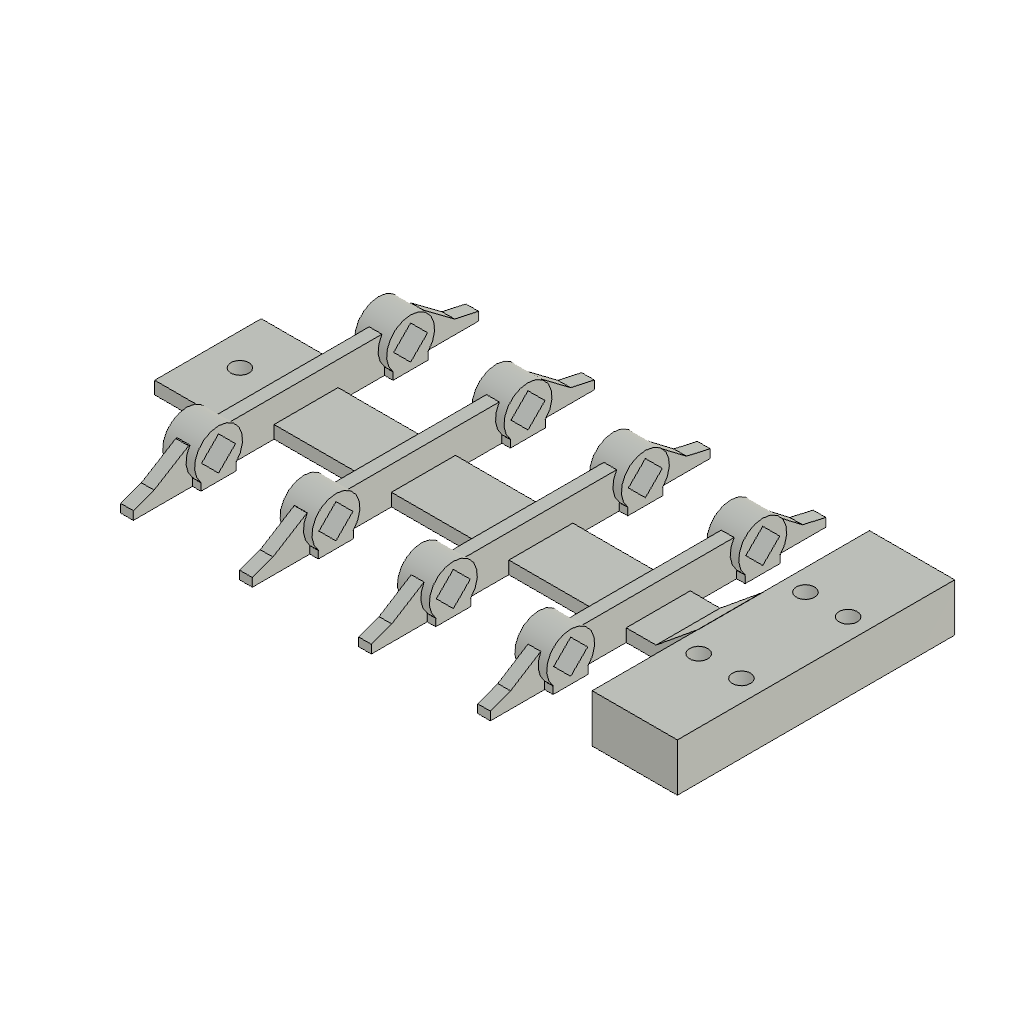
wing_tip (Autodesk Fusion 360 design; units mm, degrees)
part number: 2026-10-10-17-06-18-899
Autodesk Fusion 360 part; units mm, degrees
sketch "Continuous connecting strip sketch" plane through (0, 0, 0) normal (0, 0, 1) x (1, 0, 0)
  line L0 (0, -6) -> (114, -6)
  line L1 (114, -6) -> (114, 6)
  line L2 (114, 6) -> (0, 6)
  line L3 (0, 6) -> (0, -6)
extrude "Continuous connecting strip" add sketch "Continuous connecting strip sketch" along normal blind 2.4
ref_plane "WorkPlane1" through (16, 0, 0) normal (1, 0, 0) x (0, 1, 0)
sketch "Rib at 16 mm sketch" plane through (16, 0, 0) normal (1, 0, 0) x (0, 0, -1)
  line L0 (0, -32.3749) -> (0, 32.3749)
  line L1 (0, 32.3749) -> (-1.6, 32.3749)
  line L2 (-1.6, 32.3749) -> (-2.6, 27.8424)
  line L3 (-2.6, 27.8424) -> (-6.95, 22.0149)
  line L4 (-6.95, 22.0149) -> (-6.95, -22.0149)
  line L5 (-6.95, -22.0149) -> (-3, -28.4899)
  line L6 (-3, -28.4899) -> (-1.6, -32.3749)
  line L7 (-1.6, -32.3749) -> (0, -32.3749)
extrude "Rib at 16 mm" add sketch "Rib at 16 mm sketch" along normal blind 2.4
ref_plane "WorkPlane2" through (14, 0, 0) normal (1, 0, 0) x (0, 1, 0)
sketch "front short guide at 16 mm sketch" plane through (14, 0, 0) normal (1, 0, 0) x (0, 0, -1)
  circle A0 centre (-4.5, -18) radius 4.5
extrude "front short guide at 16 mm" add sketch "front short guide at 16 mm sketch" along normal blind 6
sketch "front guide foot at 16 mm sketch" plane through (0, 0, 0) normal (0, 0, 1) x (1, 0, 0)
  line L0 (14, -21.3) -> (20, -21.3)
  line L1 (20, -21.3) -> (20, -14.7)
  line L2 (20, -14.7) -> (14, -14.7)
  line L3 (14, -14.7) -> (14, -21.3)
extrude "front guide foot at 16 mm" add sketch "front guide foot at 16 mm sketch" along normal blind 1.4
ref_plane "WorkPlane3" through (14, 0, 0) normal (1, 0, 0) x (0, 1, 0)
sketch "rear short guide at 16 mm sketch" plane through (14, 0, 0) normal (1, 0, 0) x (0, 0, -1)
  circle A0 centre (-4.5, 18) radius 4.5
extrude "rear short guide at 16 mm" add sketch "rear short guide at 16 mm sketch" along normal blind 6
sketch "rear guide foot at 16 mm sketch" plane through (0, 0, 0) normal (0, 0, 1) x (1, 0, 0)
  line L0 (14, 14.7) -> (20, 14.7)
  line L1 (20, 14.7) -> (20, 21.3)
  line L2 (20, 21.3) -> (14, 21.3)
  line L3 (14, 21.3) -> (14, 14.7)
extrude "rear guide foot at 16 mm" add sketch "rear guide foot at 16 mm sketch" along normal blind 1.4
ref_plane "WorkPlane4" through (38, 0, 0) normal (1, 0, 0) x (0, 1, 0)
sketch "Rib at 38 mm sketch" plane through (38, 0, 0) normal (1, 0, 0) x (0, 0, -1)
  line L0 (0, -32.0662) -> (0, 32.0662)
  line L1 (0, 32.0662) -> (-1.6, 32.0662)
  line L2 (-1.6, 32.0662) -> (-2.6, 27.5769)
  line L3 (-2.6, 27.5769) -> (-6.95, 21.805)
  line L4 (-6.95, 21.805) -> (-6.95, -21.805)
  line L5 (-6.95, -21.805) -> (-3, -28.2183)
  line L6 (-3, -28.2183) -> (-1.6, -32.0662)
  line L7 (-1.6, -32.0662) -> (0, -32.0662)
extrude "Rib at 38 mm" add sketch "Rib at 38 mm sketch" along normal blind 2.4
ref_plane "WorkPlane5" through (36, 0, 0) normal (1, 0, 0) x (0, 1, 0)
sketch "front short guide at 38 mm sketch" plane through (36, 0, 0) normal (1, 0, 0) x (0, 0, -1)
  circle A0 centre (-4.5, -18) radius 4.5
extrude "front short guide at 38 mm" add sketch "front short guide at 38 mm sketch" along normal blind 6
sketch "front guide foot at 38 mm sketch" plane through (0, 0, 0) normal (0, 0, 1) x (1, 0, 0)
  line L0 (36, -21.3) -> (42, -21.3)
  line L1 (42, -21.3) -> (42, -14.7)
  line L2 (42, -14.7) -> (36, -14.7)
  line L3 (36, -14.7) -> (36, -21.3)
extrude "front guide foot at 38 mm" add sketch "front guide foot at 38 mm sketch" along normal blind 1.4
ref_plane "WorkPlane6" through (36, 0, 0) normal (1, 0, 0) x (0, 1, 0)
sketch "rear short guide at 38 mm sketch" plane through (36, 0, 0) normal (1, 0, 0) x (0, 0, -1)
  circle A0 centre (-4.5, 18) radius 4.5
extrude "rear short guide at 38 mm" add sketch "rear short guide at 38 mm sketch" along normal blind 6
sketch "rear guide foot at 38 mm sketch" plane through (0, 0, 0) normal (0, 0, 1) x (1, 0, 0)
  line L0 (36, 14.7) -> (42, 14.7)
  line L1 (42, 14.7) -> (42, 21.3)
  line L2 (42, 21.3) -> (36, 21.3)
  line L3 (36, 21.3) -> (36, 14.7)
extrude "rear guide foot at 38 mm" add sketch "rear guide foot at 38 mm sketch" along normal blind 1.4
ref_plane "WorkPlane7" through (60, 0, 0) normal (1, 0, 0) x (0, 1, 0)
sketch "Rib at 60 mm sketch" plane through (60, 0, 0) normal (1, 0, 0) x (0, 0, -1)
  line L0 (0, -31.7576) -> (0, 31.7576)
  line L1 (0, 31.7576) -> (-1.6, 31.7576)
  line L2 (-1.6, 31.7576) -> (-2.6, 27.3115)
  line L3 (-2.6, 27.3115) -> (-6.95, 21.5952)
  line L4 (-6.95, 21.5952) -> (-6.95, -21.5952)
  line L5 (-6.95, -21.5952) -> (-3, -27.9467)
  line L6 (-3, -27.9467) -> (-1.6, -31.7576)
  line L7 (-1.6, -31.7576) -> (0, -31.7576)
extrude "Rib at 60 mm" add sketch "Rib at 60 mm sketch" along normal blind 2.4
ref_plane "WorkPlane8" through (58, 0, 0) normal (1, 0, 0) x (0, 1, 0)
sketch "front short guide at 60 mm sketch" plane through (58, 0, 0) normal (1, 0, 0) x (0, 0, -1)
  circle A0 centre (-4.5, -18) radius 4.5
extrude "front short guide at 60 mm" add sketch "front short guide at 60 mm sketch" along normal blind 6
sketch "front guide foot at 60 mm sketch" plane through (0, 0, 0) normal (0, 0, 1) x (1, 0, 0)
  line L0 (58, -21.3) -> (64, -21.3)
  line L1 (64, -21.3) -> (64, -14.7)
  line L2 (64, -14.7) -> (58, -14.7)
  line L3 (58, -14.7) -> (58, -21.3)
extrude "front guide foot at 60 mm" add sketch "front guide foot at 60 mm sketch" along normal blind 1.4
ref_plane "WorkPlane9" through (58, 0, 0) normal (1, 0, 0) x (0, 1, 0)
sketch "rear short guide at 60 mm sketch" plane through (58, 0, 0) normal (1, 0, 0) x (0, 0, -1)
  circle A0 centre (-4.5, 18) radius 4.5
extrude "rear short guide at 60 mm" add sketch "rear short guide at 60 mm sketch" along normal blind 6
sketch "rear guide foot at 60 mm sketch" plane through (0, 0, 0) normal (0, 0, 1) x (1, 0, 0)
  line L0 (58, 14.7) -> (64, 14.7)
  line L1 (64, 14.7) -> (64, 21.3)
  line L2 (64, 21.3) -> (58, 21.3)
  line L3 (58, 21.3) -> (58, 14.7)
extrude "rear guide foot at 60 mm" add sketch "rear guide foot at 60 mm sketch" along normal blind 1.4
ref_plane "WorkPlane10" through (82, 0, 0) normal (1, 0, 0) x (0, 1, 0)
sketch "Rib at 82 mm sketch" plane through (82, 0, 0) normal (1, 0, 0) x (0, 0, -1)
  line L0 (0, -31.4489) -> (0, 31.4489)
  line L1 (0, 31.4489) -> (-1.6, 31.4489)
  line L2 (-1.6, 31.4489) -> (-2.6, 27.0461)
  line L3 (-2.6, 27.0461) -> (-6.95, 21.3853)
  line L4 (-6.95, 21.3853) -> (-6.95, -21.3853)
  line L5 (-6.95, -21.3853) -> (-3, -27.6751)
  line L6 (-3, -27.6751) -> (-1.6, -31.4489)
  line L7 (-1.6, -31.4489) -> (0, -31.4489)
extrude "Rib at 82 mm" add sketch "Rib at 82 mm sketch" along normal blind 2.4
ref_plane "WorkPlane11" through (80, 0, 0) normal (1, 0, 0) x (0, 1, 0)
sketch "front short guide at 82 mm sketch" plane through (80, 0, 0) normal (1, 0, 0) x (0, 0, -1)
  circle A0 centre (-4.5, -18) radius 4.5
extrude "front short guide at 82 mm" add sketch "front short guide at 82 mm sketch" along normal blind 6
sketch "front guide foot at 82 mm sketch" plane through (0, 0, 0) normal (0, 0, 1) x (1, 0, 0)
  line L0 (80, -21.3) -> (86, -21.3)
  line L1 (86, -21.3) -> (86, -14.7)
  line L2 (86, -14.7) -> (80, -14.7)
  line L3 (80, -14.7) -> (80, -21.3)
extrude "front guide foot at 82 mm" add sketch "front guide foot at 82 mm sketch" along normal blind 1.4
ref_plane "WorkPlane12" through (80, 0, 0) normal (1, 0, 0) x (0, 1, 0)
sketch "rear short guide at 82 mm sketch" plane through (80, 0, 0) normal (1, 0, 0) x (0, 0, -1)
  circle A0 centre (-4.5, 18) radius 4.5
extrude "rear short guide at 82 mm" add sketch "rear short guide at 82 mm sketch" along normal blind 6
sketch "rear guide foot at 82 mm sketch" plane through (0, 0, 0) normal (0, 0, 1) x (1, 0, 0)
  line L0 (80, 14.7) -> (86, 14.7)
  line L1 (86, 14.7) -> (86, 21.3)
  line L2 (86, 21.3) -> (80, 21.3)
  line L3 (80, 21.3) -> (80, 14.7)
extrude "rear guide foot at 82 mm" add sketch "rear guide foot at 82 mm sketch" along normal blind 1.4
sketch "Joint landing at 0 sketch" plane through (0, 0, 0) normal (0, 0, 1) x (1, 0, 0)
  line L0 (0, -10) -> (12, -10)
  line L1 (12, -10) -> (12, 10)
  line L2 (12, 10) -> (0, 10)
  line L3 (0, 10) -> (0, -10)
extrude "Joint landing at 0" add sketch "Joint landing at 0 sketch" along normal blind 2.4
ref_plane "WorkPlane13" through (0, 0, -0.05) normal (0, 0, 1) x (1, 0, 0)
sketch "Joint bolt at 6 sketch" plane through (0, 0, -0.05) normal (0, 0, 1) x (1, 0, 0)
  circle A0 centre (6, 0) radius 1.7
  dimension "d319" = 3.4
  measures "d319" diameter of A0
extrude "Joint bolt at 6" cut sketch "Joint bolt at 6 sketch" along normal blind 2.5
sketch "Tip adapter landing sketch" plane through (0, 0, 0) normal (0, 0, 1) x (1, 0, 0)
  line L0 (98, -26) -> (114, -26)
  line L1 (114, -26) -> (114, 26)
  line L2 (114, 26) -> (98, 26)
  line L3 (98, 26) -> (98, -26)
extrude "Tip adapter landing" add sketch "Tip adapter landing sketch" along normal blind 9
sketch "Tip strip shoulder sketch" plane through (0, 0, 0) normal (0, 1, 0) x (1, 0, 0)
  line L0 (90, 0) -> (98.05, 0)
  line L1 (98.05, 0) -> (98.05, -9)
  line L2 (98.05, -9) -> (90, -2.4)
  line L3 (90, -2.4) -> (90, 0)
extrude "Tip tapered strip shoulder" add sketch "Tip strip shoulder sketch" along normal mid plane 12
ref_plane "WorkPlane14" through (0, 0, -0.05) normal (0, 0, 1) x (1, 0, 0)
sketch "Tip bolt 102 -10 sketch" plane through (0, 0, -0.05) normal (0, 0, 1) x (1, 0, 0)
  circle A0 centre (102, -10) radius 1.7
  dimension "d328" = 3.4
  measures "d328" diameter of A0
extrude "Tip bolt 102 -10" cut sketch "Tip bolt 102 -10 sketch" along normal blind 9.1
ref_plane "WorkPlane15" through (0, 0, -0.05) normal (0, 0, 1) x (1, 0, 0)
sketch "Tip bolt 102 10 sketch" plane through (0, 0, -0.05) normal (0, 0, 1) x (1, 0, 0)
  circle A0 centre (102, 10) radius 1.7
  dimension "d333" = 3.4
  measures "d333" diameter of A0
extrude "Tip bolt 102 10" cut sketch "Tip bolt 102 10 sketch" along normal blind 9.1
ref_plane "WorkPlane16" through (0, 0, -0.05) normal (0, 0, 1) x (1, 0, 0)
sketch "Tip bolt 110 -10 sketch" plane through (0, 0, -0.05) normal (0, 0, 1) x (1, 0, 0)
  circle A0 centre (110, -10) radius 1.7
  dimension "d338" = 3.4
  measures "d338" diameter of A0
extrude "Tip bolt 110 -10" cut sketch "Tip bolt 110 -10 sketch" along normal blind 9.1
ref_plane "WorkPlane17" through (0, 0, -0.05) normal (0, 0, 1) x (1, 0, 0)
sketch "Tip bolt 110 10 sketch" plane through (0, 0, -0.05) normal (0, 0, 1) x (1, 0, 0)
  circle A0 centre (110, 10) radius 1.7
  dimension "d343" = 3.4
  measures "d343" diameter of A0
extrude "Tip bolt 110 10" cut sketch "Tip bolt 110 10 sketch" along normal blind 9.1
ref_plane "WorkPlane18" through (-0.05, 0, 0) normal (1, 0, 0) x (0, 1, 0)
sketch "front diamond bamboo passage sketch" plane through (-0.05, 0, 0) normal (1, 0, 0) x (0, 0, -1)
  line L0 (-4.5, -21.182) -> (-1.318, -18)
  line L1 (-1.318, -18) -> (-4.5, -14.818)
  line L2 (-4.5, -14.818) -> (-7.682, -18)
  line L3 (-7.682, -18) -> (-4.5, -21.182)
  line L4 (-4.5, -21.182) -> (-4.5, -14.818) construction
  line L5 (-1.318, -18) -> (-7.682, -18) construction
  point P0 (-4.5, -18)
  dimension "d348" = 6.364
  constraint vertical L4
  constraint horizontal L5
  constraint midpoint L4 P0
  constraint midpoint L5 P0
  constraint equal L4 L5
  measures "d348" distance of L0.end L2.end
extrude "front diamond bamboo passage" cut sketch "front diamond bamboo passage sketch" along normal blind 112.05
ref_plane "WorkPlane19" through (-0.05, 0, 0) normal (1, 0, 0) x (0, 1, 0)
sketch "rear diamond bamboo passage sketch" plane through (-0.05, 0, 0) normal (1, 0, 0) x (0, 0, -1)
  line L0 (-4.5, 14.818) -> (-1.318, 18)
  line L1 (-1.318, 18) -> (-4.5, 21.182)
  line L2 (-4.5, 21.182) -> (-7.682, 18)
  line L3 (-7.682, 18) -> (-4.5, 14.818)
  line L4 (-4.5, 14.818) -> (-4.5, 21.182) construction
  line L5 (-1.318, 18) -> (-7.682, 18) construction
  point P0 (-4.5, 18)
  dimension "d353" = 6.364
  constraint vertical L4
  constraint horizontal L5
  constraint midpoint L4 P0
  constraint midpoint L5 P0
  constraint equal L4 L5
  measures "d353" distance of L0.end L2.end
extrude "rear diamond bamboo passage" cut sketch "rear diamond bamboo passage sketch" along normal blind 112.05
equation "d249 = spanStripThickness"
equation "d315 = spanStripThickness"
equation "d319 = m3Clearance"
equation "d328 = m3Clearance"
equation "d333 = m3Clearance"
equation "d338 = m3Clearance"
equation "d343 = m3Clearance"
equation "d348 = sparBore * sqrt(2)"
equation "d353 = sparBore * sqrt(2)"
equation "sparDiameter = 4 mm" comment "Nominal bamboo diameter; choose clearance with fit coupon"
equation "sparClearance = 0.5 mm" comment "Diametral clearance; 4.5 mm coupon fit selected by user"
equation "sparBore = sparDiameter + sparClearance" comment "Flat-to-flat width of all six native diamond passages"
equation "m3Clearance = 3.4 mm" comment "Root registration and tip adapter holes"
equation "spanStripThickness = 2.4 mm" comment "Middle, tip and reinforced joint-end thickness"
named bodies: "wing_tip - printable solid"
